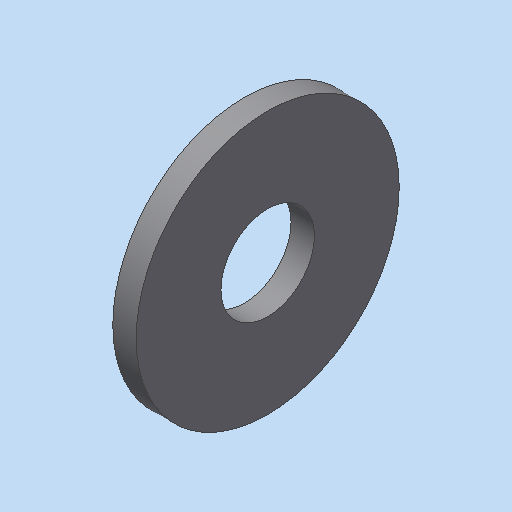
# Autodesk Inventor part: Scheibe_DIN_9021___3_2
Saved by Autodesk Inventor 2023.3 (Build 273359000, 359)
## iProperties
Shininess: 64.0
Length Units: 11269
Angle Units: 11279
Time Units: 11290
Mass Units: 11283
Length Display Precision: 3
Angle Display Precision: 2
Compacted: True
Part Number: Scheibe_DIN_9021___3_2
Document SubType Name: Modeling
Created: 2004-04-25
Description: =<RBPARTNOTITLE2>
Vendor: NORM8
Designer: C.Fischer
Manufacturer: Standard
Standards Organization: Custom
Density: 7.85 g/cm^3
Material: xStahl_AnP_Dummymaterial
Mass: 0.34901 g
Surface Area: 1.41811 cm^2
Volume: 0.0444598 cm^3
Appearance: RGB(178,178,178)
Density: 0.0
Volumn: 0.0
Area: 0.0
PropertySet Name: Model Information
Control State: 0
Master: False
Checked Out: False
CNS_NB: Scheibe DIN 9021 - 3.2
CNS_NN: DIN 9021
CNS_NT: Scheibe Aussendurchmesser = 3x Gewindenenndurchmesser
CNS_NBSYN: Scheibe DIN 9021 - $NENN.
CNS_LINA: Scheibe DIN 9021 - 3.2
CNS_NENN: 3.200
CNS_D: 3.000
CNS_DA: 3.200
CNS_DW: 9.000
CNS_H: 0.800
CNS_KT: X
PSOL_IDENT_0: {C:\partsolutions\data\23d-libs\bosch_bamberg\zubehoer\scheiben\din_9021.prj},142 {VTYP=3D},{NB=Sche
PSOL_IDENT_1: ibe DIN 9021 - 3.2},{NN=DIN 9021},{DATE=26.11.2003},{GEOMDATE=26.11.2003},{VERSION=v1},{LINEID=20},{
PSOL_IDENT_2: LINESUBID=-1},{WBVAR=}  {NB=Scheibe DIN 9021 - 3.2},{LINA=Scheibe DIN 9021 - 3.2},{KT=X},{IDNR=},{NE
PSOL_IDENT_3: NN=3.200},{D=3.000},{DA=3.200},{DW=9.000},{H=0.800}
RBPARTNOTITLE2: Karoseriescheibe, verzinkt
RBPARTNOTITLE1: Washer with large outside diameter, galvanised
RBPARTMADEOF: DIN 9021 - 3.2 - 100HV
RBDRAWINGMISSINGSPEC: --
AnP_Kategorie: 4
Title: Scheibe DIN 9021 - 3.2
Author: C.Fischer
Keywords: =<RBPARTMADEOF>
Comments: =<RBSURFACE2>
Revision Number: 01
Autodesk Inventor part; units mm, degrees
sketch "Sketch_1" plane through (0, 0, 0) normal (0, 0, 1) x (1, 0, 0)
  line L0 (0.8, 0) -> (-1.6, 0)
  line L1 (0, 4.5) -> (0, 1.6)
  line L2 (0, 1.6) -> (0.8, 1.6)
  line L3 (0.8, 1.6) -> (0.8, 4.5)
  line L4 (0.8, 4.5) -> (0, 4.5)
  constraints: 10 end point
revolve "Revolution1" add sketch "Sketch_1" angle 360 about axis through (0.8, 0, 0) along (-1, 0, 0)
ref_plane "IP1_XY" through (0, 0, 0) normal (1, 0, 0) x (0, 0, -1)
ref_plane "IP1_YZ" through (0, 0, 0) normal (0, 0, -1) x (0, 1, 0)
ref_plane "IP2_XY" through (0.8, 0, 0) normal (1, 0, 0) x (0, 0, -1)
ref_plane "IP2_YZ" through (0.8, 0, 0) normal (0, 0, -1) x (0, 1, 0)
